Autodesk Fusion 360 part; units mm, degrees
(part 2 of 4)
sketch "TUBE B01 - BACK RING BOTTOM" plane through (0, 0, 0) normal (0, 1, 0) x (1, 0, 0) in component "352307 FRONT - DECOR FRAME DR - BACK RING BOTTOM"
  line L0 (952.9368, -110) -> (1244, -110)
  line L1 (1244, -110) -> (1164, -150)
  line L2 (1164, -150) -> (967.5229, -150)
  line L3 (967.5229, -150) -> (952.9368, -110)
  point P0 (-5000, 5000)
  dimension "d9057" = 5000
  dimension "d9058" = 5000
  dimension "d9060" = 6244
  dimension "d9061" = 6164
  dimension "d9062" = 5967.5229
  dimension "d9064" = 5150
  constraint horizontal L0
  constraint horizontal L2
  measures "d9057" horizontal distance of origin P0
  measures "d9058" vertical distance of origin P0
  measures "d9060" horizontal distance of L0.end P0
  measures "d9061" horizontal distance of L1.end P0
  measures "d9062" horizontal distance of L2.end P0
  measures "d9064" vertical distance of L1.end P0
extrude "EXTRUDE - TUBE B01" add sketch "TUBE B01 - BACK RING BOTTOM" along normal blind 20 from surface at -666.5 separate body makes body 17 in component "352307 FRONT - DECOR FRAME DR - BACK RING BOTTOM"
shell "SHELL - TUBE B01 (ENDS OPEN)" thickness 1.5 removed faces 2 at (962.6609, -659.8333, 136.6667) at (1217.3333, -659.8333, 123.3333) on bodies 17 in component "352307 FRONT - DECOR FRAME DR - BACK RING BOTTOM"
sketch "TUBE B02 - BACK RING BOLT LINE" plane through (0, 0, 0) normal (0, 1, 0) x (1, 0, 0) in component "352308 FRONT - DECOR FRAME DR - BACK RING BOLT LINE"
  line L0 (1244, -110) -> (1244, -2394)
  line L1 (1244, -2394) -> (1164, -2374)
  line L2 (1164, -2374) -> (1164, -150)
  line L3 (1164, -150) -> (1244, -110)
  point P0 (-5000, 5000)
  dimension "d9069" = 5000
  dimension "d9070" = 5000
  dimension "d9071" = 6244
  dimension "d9072" = 6164
  dimension "d9076" = 5150
  constraint vertical L0
  constraint vertical L2
  measures "d9069" horizontal distance of origin P0
  measures "d9070" vertical distance of origin P0
  measures "d9071" horizontal distance of L0.start P0
  measures "d9072" horizontal distance of L1.end P0
  measures "d9076" vertical distance of L2.end P0
extrude "EXTRUDE - TUBE B02" add sketch "TUBE B02 - BACK RING BOLT LINE" along normal blind 20 from surface at -666.5 separate body makes body 18 in component "352308 FRONT - DECOR FRAME DR - BACK RING BOLT LINE"
shell "SHELL - TUBE B02 (ENDS OPEN)" thickness 1.5 removed faces 2 at (1190.6667, -659.8333, 136.6667) at (1217.3333, -659.8333, 2387.3333) on bodies 18 in component "352308 FRONT - DECOR FRAME DR - BACK RING BOLT LINE"
sketch "TUBE B03 - BACK RING TOP" plane through (0, 0, 0) normal (0, 1, 0) x (1, 0, 0) in component "352309 FRONT - DECOR FRAME DR - BACK RING TOP"
  line L0 (1244, -2394) -> (449, -2394)
  line L1 (449, -2394) -> (469, -2374)
  line L2 (469, -2374) -> (1164, -2374)
  line L3 (1164, -2374) -> (1244, -2394)
  point P0 (-5000, 5000)
  dimension "d9081" = 5000
  dimension "d9082" = 5000
  dimension "d9083" = 6244
  dimension "d9084" = 5449
  dimension "d9085" = 5469
  dimension "d9086" = 6164
  constraint horizontal L0
  constraint horizontal L2
  measures "d9081" horizontal distance of origin P0
  measures "d9082" vertical distance of origin P0
  measures "d9083" horizontal distance of L0.start P0
  measures "d9084" horizontal distance of L0.end P0
  measures "d9085" horizontal distance of L1.end P0
  measures "d9086" horizontal distance of L2.end P0
extrude "EXTRUDE - TUBE B03" add sketch "TUBE B03 - BACK RING TOP" along normal blind 20 from surface at -666.5 separate body makes body 19 in component "352309 FRONT - DECOR FRAME DR - BACK RING TOP"
shell "SHELL - TUBE B03 (ENDS OPEN)" thickness 1 removed faces 2 at (1190.6667, -659.8333, 2380.6667) at (455.6667, -659.8333, 2387.3333) on bodies 19 in component "352309 FRONT - DECOR FRAME DR - BACK RING TOP"
sketch "TUBE B04 - BACK RING DT JOINT" plane through (0, 0, 0) normal (0, 1, 0) x (1, 0, 0) in component "352310 FRONT - DECOR FRAME DR - BACK RING DT JOINT"
  line L0 (449, -2394) -> (449, -2120)
  line L1 (449, -2120) -> (469, -2100)
  line L2 (469, -2100) -> (469, -2374)
  line L3 (469, -2374) -> (449, -2394)
  point P0 (-5000, 5000)
  dimension "d9093" = 5000
  dimension "d9094" = 5000
  dimension "d9095" = 5449
  dimension "d9096" = 5469
  dimension "d9099" = 7100
  constraint vertical L0
  constraint vertical L2
  measures "d9093" horizontal distance of origin P0
  measures "d9094" vertical distance of origin P0
  measures "d9095" horizontal distance of L0.start P0
  measures "d9096" horizontal distance of L1.end P0
  measures "d9099" vertical distance of L1.end P0
extrude "EXTRUDE - TUBE B04" add sketch "TUBE B04 - BACK RING DT JOINT" along normal blind 20 from surface at -666.5 separate body makes body 20 in component "352310 FRONT - DECOR FRAME DR - BACK RING DT JOINT"
shell "SHELL - TUBE B04 (ENDS OPEN)" thickness 1 removed faces 2 at (462.3333, -653.1667, 2380.6667) at (455.6667, -653.1667, 2113.3333) on bodies 20 in component "352310 FRONT - DECOR FRAME DR - BACK RING DT JOINT"
sketch "TUBE B05 - BACK RING DT LEDGE" plane through (0, 0, 0) normal (0, 1, 0) x (1, 0, 0) in component "352311 FRONT - DECOR FRAME DR - BACK RING DT LEDGE"
  line L0 (449, -2120) -> (237.9389, -2120)
  line L1 (237.9389, -2120) -> (281.7308, -2100)
  line L2 (281.7308, -2100) -> (469, -2100)
  line L3 (469, -2100) -> (449, -2120)
  point P0 (-5000, 5000)
  dimension "d9105" = 5000
  dimension "d9106" = 5000
  dimension "d9107" = 5449
  dimension "d9108" = 5237.9389
  dimension "d9109" = 5281.7308
  dimension "d9110" = 5469
  dimension "d9112" = 7100
  constraint horizontal L0
  constraint horizontal L2
  measures "d9105" horizontal distance of origin P0
  measures "d9106" vertical distance of origin P0
  measures "d9107" horizontal distance of L0.start P0
  measures "d9108" horizontal distance of L0.end P0
  measures "d9109" horizontal distance of L1.end P0
  measures "d9110" horizontal distance of L2.end P0
  measures "d9112" vertical distance of L1.end P0
extrude "EXTRUDE - TUBE B05" add sketch "TUBE B05 - BACK RING DT LEDGE" along normal blind 20 from surface at -666.5 separate body makes body 21 in component "352311 FRONT - DECOR FRAME DR - BACK RING DT LEDGE"
shell "SHELL - TUBE B05 (ENDS OPEN)" thickness 1.5 removed faces 2 at (462.3333, -659.8333, 2106.6667) at (252.5362, -659.8333, 2113.3333) on bodies 21 in component "352311 FRONT - DECOR FRAME DR - BACK RING DT LEDGE"
sketch "TUBE B06 - BACK RING DIAGONAL" plane through (0, 0, 0) normal (0, 1, 0) x (1, 0, 0) in component "352312 FRONT - DECOR FRAME DR - BACK RING DIAGONAL"
  line L0 (237.9389, -2120) -> (754.6956, -1523.5891)
  line L1 (754.6956, -1523.5891) -> (773.681, -1532.2192)
  line L2 (773.681, -1532.2192) -> (281.7308, -2100)
  line L3 (281.7308, -2100) -> (237.9389, -2120)
  point P0 (-5000, 5000)
  dimension "d9117" = 5000
  dimension "d9118" = 5000
  dimension "d9119" = 5237.9389
  dimension "d9120" = 5754.6956
  dimension "d9121" = 5773.681
  dimension "d9122" = 5281.7308
  dimension "d9124" = 6523.5891
  dimension "d9125" = 6532.2192
  dimension "d9126" = 7100
  measures "d9117" horizontal distance of origin P0
  measures "d9118" vertical distance of origin P0
  measures "d9119" horizontal distance of L0.start P0
  measures "d9120" horizontal distance of L0.end P0
  measures "d9121" horizontal distance of L1.end P0
  measures "d9122" horizontal distance of L2.end P0
  measures "d9124" vertical distance of L0.end P0
  measures "d9125" vertical distance of L1.end P0
  measures "d9126" vertical distance of L2.end P0
extrude "EXTRUDE - TUBE B06" add sketch "TUBE B06 - BACK RING DIAGONAL" along normal blind 20 from surface at -666.5 separate body makes body 22 in component "352312 FRONT - DECOR FRAME DR - BACK RING DIAGONAL"
shell "SHELL - TUBE B06 (ENDS OPEN)" thickness 1.5 removed faces 2 at (267.1335, -659.8333, 2106.6667) at (761.0241, -659.8333, 1526.4658) on bodies 22 in component "352312 FRONT - DECOR FRAME DR - BACK RING DIAGONAL"
sketch "TUBE B07 - BACK RING GLASS EDGE" plane through (0, 0, 0) normal (0, 1, 0) x (1, 0, 0) in component "352313 FRONT - DECOR FRAME DR - BACK RING GLASS EDGE"
  line L0 (754.6956, -1523.5891) -> (952.9368, -110)
  line L1 (952.9368, -110) -> (967.5229, -150)
  line L2 (967.5229, -150) -> (773.681, -1532.2192)
  line L3 (773.681, -1532.2192) -> (754.6956, -1523.5891)
  point P0 (-5000, 5000)
  dimension "d9131" = 5000
  dimension "d9132" = 5000
  dimension "d9133" = 5754.6956
  dimension "d9135" = 5967.5229
  dimension "d9136" = 5773.681
  dimension "d9137" = 6523.5891
  dimension "d9139" = 5150
  dimension "d9140" = 6532.2192
  measures "d9131" horizontal distance of origin P0
  measures "d9132" vertical distance of origin P0
  measures "d9133" horizontal distance of L0.start P0
  measures "d9135" horizontal distance of L1.end P0
  measures "d9136" horizontal distance of L2.end P0
  measures "d9137" vertical distance of L0.start P0
  measures "d9139" vertical distance of L1.end P0
  measures "d9140" vertical distance of L2.end P0
extrude "EXTRUDE - TUBE B07" add sketch "TUBE B07 - BACK RING GLASS EDGE" along normal blind 20 from surface at -666.5 separate body makes body 23 in component "352313 FRONT - DECOR FRAME DR - BACK RING GLASS EDGE"
shell "SHELL - TUBE B07 (ENDS OPEN)" thickness 1.5 removed faces 2 at (767.3526, -659.8333, 1529.3425) at (957.7988, -659.8333, 123.3333) on bodies 23 in component "352313 FRONT - DECOR FRAME DR - BACK RING GLASS EDGE"
sketch "TUBE F07 - FRONT RING CROSS 724" plane through (0, 0, 0) normal (0, 1, 0) x (1, 0, 0) in component "352314 FRONT - DECOR FRAME DR - FRONT RING CROSS 724"
  line L0 (871.599, -834) -> (1029.6995, -834)
  line L1 (1029.6995, -834) -> (1029.6995, -854)
  line L2 (1029.6995, -854) -> (868.7942, -854)
  line L3 (868.7942, -854) -> (871.599, -834)
  point P0 (-5000, 5000)
  dimension "d9145" = 5000
  dimension "d9146" = 5000
  dimension "d9147" = 5871.599
  dimension "d9148" = 6029.6995
  dimension "d9149" = 5868.7942
  dimension "d9150" = 5834
  dimension "d9151" = 5854
  constraint vertical L1
  constraint horizontal L0
  constraint horizontal L2
  measures "d9145" horizontal distance of origin P0
  measures "d9146" vertical distance of origin P0
  measures "d9147" horizontal distance of L0.start P0
  measures "d9148" horizontal distance of L0.end P0
  measures "d9149" horizontal distance of L2.end P0
  measures "d9150" vertical distance of L0.start P0
  measures "d9151" vertical distance of L1.end P0
extrude "EXTRUDE - TUBE F07" add sketch "TUBE F07 - FRONT RING CROSS 724" along normal blind 20 from surface at -844 separate body makes body 24 in component "352314 FRONT - DECOR FRAME DR - FRONT RING CROSS 724"
shell "SHELL - TUBE F07 (ENDS OPEN)" thickness 1 removed faces 2 at (869.7292, -837.3333, 847.3333) at (1029.6995, -837.3333, 840.6667) on bodies 24 in component "352314 FRONT - DECOR FRAME DR - FRONT RING CROSS 724"
sketch "TUBE F08 - FRONT RING FAN BOX SHELF" plane through (0, 0, 0) normal (0, 1, 0) x (1, 0, 0) in component "352315 FRONT - DECOR FRAME DR - FRONT RING FAN BOX SHELF"
  line L0 (688.9595, -1630) -> (1029.6995, -1630)
  line L1 (1029.6995, -1630) -> (1029.6995, -1650)
  line L2 (1029.6995, -1650) -> (671.6306, -1650)
  line L3 (671.6306, -1650) -> (688.9595, -1630)
  point P0 (-5000, 5000)
  dimension "d9156" = 5000
  dimension "d9157" = 5000
  dimension "d9158" = 5688.9595
  dimension "d9159" = 6029.6995
  dimension "d9160" = 5671.6306
  dimension "d9161" = 6630
  dimension "d9162" = 6650
  constraint vertical L1
  constraint horizontal L0
  constraint horizontal L2
  measures "d9156" horizontal distance of origin P0
  measures "d9157" vertical distance of origin P0
  measures "d9158" horizontal distance of L0.start P0
  measures "d9159" horizontal distance of L0.end P0
  measures "d9160" horizontal distance of L2.end P0
  measures "d9161" vertical distance of L0.start P0
  measures "d9162" vertical distance of L1.end P0
extrude "EXTRUDE - TUBE F08" add sketch "TUBE F08 - FRONT RING FAN BOX SHELF" along normal blind 20 from surface at -844 separate body makes body 25 in component "352315 FRONT - DECOR FRAME DR - FRONT RING FAN BOX SHELF"
shell "SHELL - TUBE F08 (ENDS OPEN)" thickness 1.5 removed faces 2 at (677.4069, -837.3333, 1643.3333) at (1029.6995, -837.3333, 1636.6667) on bodies 25 in component "352315 FRONT - DECOR FRAME DR - FRONT RING FAN BOX SHELF"
sketch "TUBE F09 - FRONT RING CROSS OVER THE FAN BOX" plane through (0, 0, 0) normal (0, 1, 0) x (1, 0, 0) in component "352322 FRONT - DECOR FRAME DR - FRONT RING CROSS OVER THE FAN BOX"
  line L0 (451.6766, -1903.8583) -> (1029.6995, -1903.8583)
  line L1 (1029.6995, -1903.8583) -> (1029.6995, -1923.8583)
  line L2 (1029.6995, -1923.8583) -> (434.3477, -1923.8583)
  line L3 (434.3477, -1923.8583) -> (451.6766, -1903.8583)
  point P0 (-5000, 5000)
  dimension "d9167" = 5000
  dimension "d9168" = 5000
  dimension "d9169" = 5451.6766
  dimension "d9170" = 6029.6995
  dimension "d9171" = 5434.3477
  dimension "d9172" = 6903.8583
  dimension "d9173" = 6923.8583
  constraint vertical L1
  constraint horizontal L0
  constraint horizontal L2
  measures "d9167" horizontal distance of origin P0
  measures "d9168" vertical distance of origin P0
  measures "d9169" horizontal distance of L0.start P0
  measures "d9170" horizontal distance of L0.end P0
  measures "d9171" horizontal distance of L2.end P0
  measures "d9172" vertical distance of L0.start P0
  measures "d9173" vertical distance of L1.end P0
extrude "EXTRUDE - TUBE F09" add sketch "TUBE F09 - FRONT RING CROSS OVER THE FAN BOX" along normal blind 20 from surface at -844 separate body makes body 26 in component "352322 FRONT - DECOR FRAME DR - FRONT RING CROSS OVER THE FAN BOX"
shell "SHELL - TUBE F09 (ENDS OPEN)" thickness 1 removed faces 2 at (440.124, -837.3333, 1917.1917) at (1029.6995, -837.3333, 1910.525) on bodies 26 in component "352322 FRONT - DECOR FRAME DR - FRONT RING CROSS OVER THE FAN BOX"
sketch "TUBE B08 - BACK RING BAND" plane through (0, 0, 0) normal (0, 1, 0) x (1, 0, 0) in component "352316 FRONT - DECOR FRAME DR - BACK RING BAND"
  line L0 (469, -2120) -> (1164, -2120)
  line L1 (1164, -2120) -> (1164, -2180)
  line L2 (1164, -2180) -> (469, -2180)
  line L3 (469, -2180) -> (469, -2120)
  point P0 (-5000, 5000)
  dimension "d9178" = 5000
  dimension "d9179" = 5000
  dimension "d9180" = 6164
  dimension "d9181" = 5469
  constraint vertical L1
  constraint vertical L3
  constraint horizontal L0
  constraint horizontal L2
  measures "d9178" horizontal distance of origin P0
  measures "d9179" vertical distance of origin P0
  measures "d9180" horizontal distance of L0.end P0
  measures "d9181" horizontal distance of L2.end P0
extrude "EXTRUDE - TUBE B08" add sketch "TUBE B08 - BACK RING BAND" along normal blind 20 from surface at -666.5 separate body makes body 27 in component "352316 FRONT - DECOR FRAME DR - BACK RING BAND"
shell "SHELL - TUBE B08 (ENDS OPEN)" thickness 1.5 removed faces 2 at (469, -659.8333, 2160) at (1164, -659.8333, 2140) on bodies 27 in component "352316 FRONT - DECOR FRAME DR - BACK RING BAND"
sketch "TUBE C01 - FACET TUBE BOTTOM" plane through (0, 0, 0) normal (0, 0, 1) x (1, 0, 0) in component "352317 FRONT - DECOR FRAME DR - FACET TUBE - 3 OFF"
  line L0 (1049.6995, -844) -> (1244, -669.3258)
  line L1 (1244, -669.3258) -> (1244, -666.5)
  line L2 (1244, -666.5) -> (1217.2278, -666.5)
  line L3 (1217.2278, -666.5) -> (1049.6995, -817.1063)
  line L4 (1049.6995, -817.1063) -> (1049.6995, -844)
  point P0 (-5000, -5000)
  dimension "d9188" = 5000
  dimension "d9189" = 5000
  dimension "d9190" = 6244
  dimension "d9191" = 6217.2278
  dimension "d9192" = 6049.6995
  dimension "d9193" = 4156
  dimension "d9194" = 4330.6742
  dimension "d9195" = 4333.5
  dimension "d9196" = 4182.8937
  constraint vertical L1
  constraint vertical L4
  constraint horizontal L2
  measures "d9188" horizontal distance of origin P0
  measures "d9189" vertical distance of origin P0
  measures "d9190" horizontal distance of L0.end P0
  measures "d9191" horizontal distance of L2.end P0
  measures "d9192" horizontal distance of L3.end P0
  measures "d9193" vertical distance of L0.start P0
  measures "d9194" vertical distance of L0.end P0
  measures "d9195" vertical distance of L1.end P0
  measures "d9196" vertical distance of L3.end P0
extrude "EXTRUDE - TUBE C01" add sketch "TUBE C01 - FACET TUBE BOTTOM" along normal blind 20 from surface at 110 separate body makes body 28 in component "352317 FRONT - DECOR FRAME DR - FACET TUBE - 3 OFF"
shell "SHELL - TUBE C01 (ENDS OPEN)" thickness 1 removed faces 3 at (1235.0759, -666.5, 123.3333) at (1244, -668.3839, 116.6667) at (1049.6995, -826.0708, 116.6667) on bodies 28 in component "352317 FRONT - DECOR FRAME DR - FACET TUBE - 3 OFF"
sketch "TUBE C03 - FACET TUBE FAN BOX SHELF" plane through (0, 0, 0) normal (0, 0, 1) x (1, 0, 0) in component "352318 FRONT - DECOR FRAME DR - FACET TUBE FAN BOX SHELF"
  line L0 (1049.6995, -844) -> (1244, -669.3258)
  line L1 (1244, -669.3258) -> (1244, -666.5)
  line L2 (1244, -666.5) -> (1217.2278, -666.5)
  line L3 (1217.2278, -666.5) -> (1049.6995, -817.1063)
  line L4 (1049.6995, -817.1063) -> (1049.6995, -844)
  point P0 (-5000, -5000)
  dimension "d9201" = 5000
  dimension "d9202" = 5000
  dimension "d9203" = 6244
  dimension "d9204" = 6217.2278
  dimension "d9205" = 6049.6995
  dimension "d9206" = 4156
  dimension "d9207" = 4330.6742
  dimension "d9208" = 4333.5
  dimension "d9209" = 4182.8937
  constraint vertical L1
  constraint vertical L4
  constraint horizontal L2
  measures "d9201" horizontal distance of origin P0
  measures "d9202" vertical distance of origin P0
  measures "d9203" horizontal distance of L0.end P0
  measures "d9204" horizontal distance of L2.end P0
  measures "d9205" horizontal distance of L3.end P0
  measures "d9206" vertical distance of L0.start P0
  measures "d9207" vertical distance of L0.end P0
  measures "d9208" vertical distance of L1.end P0
  measures "d9209" vertical distance of L3.end P0
extrude "EXTRUDE - TUBE C03" add sketch "TUBE C03 - FACET TUBE FAN BOX SHELF" along normal blind 20 from surface at 1630 separate body makes body 29 in component "352318 FRONT - DECOR FRAME DR - FACET TUBE FAN BOX SHELF"
shell "SHELL - TUBE C03 (ENDS OPEN)" thickness 1.5 removed faces 3 at (1235.0759, -666.5, 1643.3333) at (1244, -668.3839, 1636.6667) at (1049.6995, -826.0708, 1636.6667) on bodies 29 in component "352318 FRONT - DECOR FRAME DR - FACET TUBE FAN BOX SHELF"
ref_plane "WorkPlane1" through (0, 0, 1820) normal (0, 0, 1) x (1, 0, 0) in component "351306 FRONT - DECOR FRAME - DR"
ref_plane "WorkPlane2" through (0, 0, 2067.7167) normal (0, 0, 1) x (1, 0, 0) in component "351306 FRONT - DECOR FRAME - DR"
sketch "TUBE C06 - CHAMFER TUBE LEFT" plane through (0, 0, 0) normal (1, 0, 0) x (0, 0, -1) in component "352319 FRONT - DECOR FRAME DR - CHAMFER TUBE - 2 OFF"
  line L0 (-2197.7167, -844) -> (-2394, -669.3078)
  line L1 (-2394, -669.3078) -> (-2394, -666.5)
  line L2 (-2394, -666.5) -> (-2367.0719, -666.5)
  line L3 (-2367.0719, -666.5) -> (-2197.7167, -817.2261)
  line L4 (-2197.7167, -817.2261) -> (-2197.7167, -844)
  point P0 (5000, -5000)
  dimension "d9226" = 5000
  dimension "d9227" = 5000
  dimension "d9229" = 7367.0719
  dimension "d9230" = 7197.7167
  dimension "d9231" = 4156
  dimension "d9232" = 4330.6922
  dimension "d9233" = 4333.5
  dimension "d9234" = 4182.7739
  constraint vertical L1
  constraint vertical L4
  constraint horizontal L2
  measures "d9226" horizontal distance of origin P0
  measures "d9227" vertical distance of origin P0
  measures "d9229" horizontal distance of L2.end P0
  measures "d9230" horizontal distance of L3.end P0
  measures "d9231" vertical distance of L0.start P0
  measures "d9232" vertical distance of L0.end P0
  measures "d9233" vertical distance of L1.end P0
  measures "d9234" vertical distance of L3.end P0
extrude "EXTRUDE - TUBE C06" add sketch "TUBE C06 - CHAMFER TUBE LEFT" along normal blind 20 from surface at 469 separate body makes body 30 in component "352319 FRONT - DECOR FRAME DR - CHAMFER TUBE - 2 OFF"
shell "SHELL - TUBE C06 (ENDS OPEN)" thickness 1 removed faces 3 at (475.6667, -826.1508, 2197.7167) at (482.3333, -668.3719, 2394) at (482.3333, -666.5, 2385.024) on bodies 30 in component "352319 FRONT - DECOR FRAME DR - CHAMFER TUBE - 2 OFF"
ref_plane "WorkPlane3" through (540.6995, 0, 0) normal (1, 0, 0) x (0, 1, 0) in component "351306 FRONT - DECOR FRAME - DR"
sketch "TUBE C09 - DT JOINT TUBE SLANTED" plane through (0, 0, 0) normal (0, 0, 1) x (1, 0, 0) in component "352320 FRONT - DECOR FRAME DR - DT JOINT TUBE SLANTED"
  line L0 (261.9888, -824) -> (455.7669, -666.5)
  line L1 (455.7669, -666.5) -> (487.4763, -666.5)
  line L2 (487.4763, -666.5) -> (293.6983, -824)
  line L3 (293.6983, -824) -> (261.9888, -824)
  point P0 (-5000, -5000)
  dimension "d9245" = 5000
  dimension "d9246" = 5000
  dimension "d9247" = 5261.9888
  dimension "d9248" = 5455.7669
  dimension "d9249" = 5487.4763
  dimension "d9250" = 5293.6983
  dimension "d9251" = 4333.5
  dimension "d9252" = 4176
  constraint horizontal L1
  constraint horizontal L3
  measures "d9245" horizontal distance of origin P0
  measures "d9246" vertical distance of origin P0
  measures "d9247" horizontal distance of L0.start P0
  measures "d9248" horizontal distance of L0.end P0
  measures "d9249" horizontal distance of L1.end P0
  measures "d9250" horizontal distance of L2.end P0
  measures "d9251" vertical distance of L0.end P0
  measures "d9252" vertical distance of L2.end P0
extrude "EXTRUDE - TUBE C09" add sketch "TUBE C09 - DT JOINT TUBE SLANTED" along normal blind 20 from surface at 2120 separate body makes body 31 in component "352320 FRONT - DECOR FRAME DR - DT JOINT TUBE SLANTED"
shell "SHELL - TUBE C09 (ENDS OPEN)" thickness 1 removed faces 2 at (283.1284, -824, 2126.6667) at (466.3367, -666.5, 2133.3333) on bodies 31 in component "352320 FRONT - DECOR FRAME DR - DT JOINT TUBE SLANTED"
sketch "HOLES - J-FRONT-01 RIVNUT TAILS AND BOLT TIPS (6)" plane through (0, 0, 0) normal (0, 1, 0) x (1, 0, 0) in component "352308 FRONT - DECOR FRAME DR - BACK RING BOLT LINE"
  circle A0 centre (1224, -332.26) radius 7
  circle A1 centre (1224, -683.63) radius 7
  circle A2 centre (1224, -1035) radius 7
  circle A3 centre (1224, -1477.26) radius 7
  circle A4 centre (1224, -1828.63) radius 7
  circle A5 centre (1224, -2180) radius 7
  point P0 (-5000, 5000)
  dimension "d9257" = 5000
  dimension "d9258" = 5000
  dimension "d9260" = 5332.26
  dimension "d9261" = 14
  dimension "d9263" = 5683.63
  dimension "d9264" = 14
  dimension "d9266" = 6035
  dimension "d9267" = 14
  dimension "d9269" = 6477.26
  dimension "d9270" = 14
  dimension "d9272" = 6828.63
  dimension "d9273" = 14
  dimension "d9275" = 7180
  dimension "d9276" = 14
  measures "d9257" horizontal distance of origin P0
  measures "d9258" vertical distance of origin P0
  measures "d9260" vertical distance of P0 A0.centre
  measures "d9261" diameter of A0
  measures "d9263" vertical distance of P0 A1.centre
  measures "d9264" diameter of A1
  measures "d9266" vertical distance of P0 A2.centre
  measures "d9267" diameter of A2
  measures "d9269" vertical distance of P0 A3.centre
  measures "d9270" diameter of A3
  measures "d9272" vertical distance of P0 A4.centre
  measures "d9273" diameter of A4
  measures "d9275" vertical distance of P0 A5.centre
  measures "d9276" diameter of A5
extrude "CUT - J-FRONT-01 RIVNUT TAILS AND BOLT TIPS (6)" cut sketch "HOLES - J-FRONT-01 RIVNUT TAILS AND BOLT TIPS (6)" along normal blind 3 from surface at -649 bodies 18 in component "352308 FRONT - DECOR FRAME DR - BACK RING BOLT LINE"
sketch "HOLES - THE INNER FACE PANEL'S RIVNUTS ON B01 (2)" plane through (0, 0, 0) normal (0, 1, 0) x (1, 0, 0) in component "352307 FRONT - DECOR FRAME DR - BACK RING BOTTOM"
  circle A0 centre (1000.2299, -130) radius 5
  circle A1 centre (1146, -130) radius 5
  point P0 (-5000, 5000)
  dimension "d9280" = 5000
  dimension "d9281" = 5000
  dimension "d9282" = 6000.2299
  dimension "d9283" = 5130
  dimension "d9284" = 10
  dimension "d9285" = 6146
  dimension "d9286" = 5130
  dimension "d9287" = 10
  measures "d9280" horizontal distance of origin P0
  measures "d9281" vertical distance of origin P0
  measures "d9282" horizontal distance of P0 A0.centre
  measures "d9283" vertical distance of P0 A0.centre
  measures "d9284" diameter of A0
  measures "d9285" horizontal distance of P0 A1.centre
  measures "d9286" vertical distance of P0 A1.centre
  measures "d9287" diameter of A1
extrude "CUT - THE INNER FACE PANEL'S RIVNUTS ON B01 (2)" cut sketch "HOLES - THE INNER FACE PANEL'S RIVNUTS ON B01 (2)" along normal blind 3 from surface at -649 bodies 17 in component "352307 FRONT - DECOR FRAME DR - BACK RING BOTTOM"
sketch "HOLES - THE INNER FACE PANEL'S RIVNUTS ON B02 (6)" plane through (0, 0, 0) normal (0, 1, 0) x (1, 0, 0) in component "352308 FRONT - DECOR FRAME DR - BACK RING BOLT LINE"
  circle A0 centre (1186, -170) radius 5
  circle A1 centre (1186, -556.2) radius 5
  circle A2 centre (1186, -942.4) radius 5
  circle A3 centre (1186, -1328.6) radius 5
  circle A4 centre (1186, -1714.8) radius 5
  circle A5 centre (1186, -2101) radius 5
  point P0 (-5000, 5000)
  dimension "d9291" = 5000
  dimension "d9292" = 5000
  dimension "d9293" = 6186
  dimension "d9294" = 5170
  dimension "d9295" = 10
  dimension "d9296" = 6186
  dimension "d9297" = 5556.2
  dimension "d9298" = 10
  dimension "d9299" = 6186
  dimension "d9300" = 5942.4
  dimension "d9301" = 10
  dimension "d9302" = 6186
  dimension "d9303" = 6328.6
  dimension "d9304" = 10
  dimension "d9305" = 6186
  dimension "d9306" = 6714.8
  dimension "d9307" = 10
  dimension "d9308" = 6186
  dimension "d9309" = 7101
  dimension "d9310" = 10
  measures "d9291" horizontal distance of origin P0
  measures "d9292" vertical distance of origin P0
  measures "d9293" horizontal distance of P0 A0.centre
  measures "d9294" vertical distance of P0 A0.centre
  measures "d9295" diameter of A0
  measures "d9296" horizontal distance of P0 A1.centre
  measures "d9297" vertical distance of P0 A1.centre
  measures "d9298" diameter of A1
  measures "d9299" horizontal distance of P0 A2.centre
  measures "d9300" vertical distance of P0 A2.centre
  measures "d9301" diameter of A2
  measures "d9302" horizontal distance of P0 A3.centre
  measures "d9303" vertical distance of P0 A3.centre
  measures "d9304" diameter of A3
  measures "d9305" horizontal distance of P0 A4.centre
  measures "d9306" vertical distance of P0 A4.centre
  measures "d9307" diameter of A4
  measures "d9308" horizontal distance of P0 A5.centre
  measures "d9309" vertical distance of P0 A5.centre
  measures "d9310" diameter of A5
extrude "CUT - THE INNER FACE PANEL'S RIVNUTS ON B02 (6)" cut sketch "HOLES - THE INNER FACE PANEL'S RIVNUTS ON B02 (6)" along normal blind 3 from surface at -649 bodies 18 in component "352308 FRONT - DECOR FRAME DR - BACK RING BOLT LINE"
sketch "HOLES - THE INNER FACE PANEL'S RIVNUTS ON B08 (3)" plane through (0, 0, 0) normal (0, 1, 0) x (1, 0, 0) in component "352316 FRONT - DECOR FRAME DR - BACK RING BAND"
  circle A0 centre (1143.5, -2141) radius 5
  circle A1 centre (821.25, -2141) radius 5
  circle A2 centre (499, -2141) radius 5
  point P0 (-5000, 5000)
  dimension "d9314" = 5000
  dimension "d9315" = 5000
  dimension "d9316" = 6143.5
  dimension "d9317" = 7141
  dimension "d9318" = 10
  dimension "d9319" = 5821.25
  dimension "d9320" = 7141
  dimension "d9321" = 10
  dimension "d9322" = 5499
  dimension "d9323" = 7141
  dimension "d9324" = 10
  measures "d9314" horizontal distance of origin P0
  measures "d9315" vertical distance of origin P0
  measures "d9316" horizontal distance of P0 A0.centre
  measures "d9317" vertical distance of P0 A0.centre
  measures "d9318" diameter of A0
  measures "d9319" horizontal distance of P0 A1.centre
  measures "d9320" vertical distance of P0 A1.centre
  measures "d9321" diameter of A1
  measures "d9322" horizontal distance of P0 A2.centre
  measures "d9323" vertical distance of P0 A2.centre
  measures "d9324" diameter of A2
extrude "CUT - THE INNER FACE PANEL'S RIVNUTS ON B08 (3)" cut sketch "HOLES - THE INNER FACE PANEL'S RIVNUTS ON B08 (3)" along normal blind 3 from surface at -649 bodies 27 in component "352316 FRONT - DECOR FRAME DR - BACK RING BAND"
sketch "HOLES - THE INNER FACE PANEL'S RIVNUTS ON B05 (2)" plane through (0, 0, 0) normal (0, 1, 0) x (1, 0, 0) in component "352311 FRONT - DECOR FRAME DR - BACK RING DT LEDGE"
  circle A0 centre (419, -2110) radius 5
  circle A1 centre (299.8348, -2110) radius 5
  point P0 (-5000, 5000)
  dimension "d9328" = 5000
  dimension "d9329" = 5000
  dimension "d9330" = 5419
  dimension "d9331" = 7110
  dimension "d9332" = 10
  dimension "d9333" = 5299.8348
  dimension "d9334" = 7110
  dimension "d9335" = 10
  measures "d9328" horizontal distance of origin P0
  measures "d9329" vertical distance of origin P0
  measures "d9330" horizontal distance of P0 A0.centre
  measures "d9331" vertical distance of P0 A0.centre
  measures "d9332" diameter of A0
  measures "d9333" horizontal distance of P0 A1.centre
  measures "d9334" vertical distance of P0 A1.centre
  measures "d9335" diameter of A1
extrude "CUT - THE INNER FACE PANEL'S RIVNUTS ON B05 (2)" cut sketch "HOLES - THE INNER FACE PANEL'S RIVNUTS ON B05 (2)" along normal blind 3 from surface at -649 bodies 21 in component "352311 FRONT - DECOR FRAME DR - BACK RING DT LEDGE"
sketch "HOLES - THE INNER FACE PANEL'S RIVNUTS ON B06 (3)" plane through (0, 0, 0) normal (0, 1, 0) x (1, 0, 0) in component "352312 FRONT - DECOR FRAME DR - BACK RING DIAGONAL"
  circle A0 centre (286.0282, -2079.7691) radius 5
  circle A1 centre (512.0116, -1818.9521) radius 5
  circle A2 centre (737.995, -1558.135) radius 5
  point P0 (-5000, 5000)
  dimension "d9339" = 5000
  dimension "d9340" = 5000
  dimension "d9341" = 5286.0282
  dimension "d9342" = 7079.7691
  dimension "d9343" = 10
  dimension "d9344" = 5512.0116
  dimension "d9345" = 6818.9521
  dimension "d9346" = 10
  dimension "d9347" = 5737.995
  dimension "d9348" = 6558.135
  dimension "d9349" = 10
  measures "d9339" horizontal distance of origin P0
  measures "d9340" vertical distance of origin P0
  measures "d9341" horizontal distance of P0 A0.centre
  measures "d9342" vertical distance of P0 A0.centre
  measures "d9343" diameter of A0
  measures "d9344" horizontal distance of P0 A1.centre
  measures "d9345" vertical distance of P0 A1.centre
  measures "d9346" diameter of A1
  measures "d9347" horizontal distance of P0 A2.centre
  measures "d9348" vertical distance of P0 A2.centre
  measures "d9349" diameter of A2
extrude "CUT - THE INNER FACE PANEL'S RIVNUTS ON B06 (3)" cut sketch "HOLES - THE INNER FACE PANEL'S RIVNUTS ON B06 (3)" along normal blind 3 from surface at -649 bodies 22 in component "352312 FRONT - DECOR FRAME DR - BACK RING DIAGONAL"
sketch "HOLES - THE INNER FACE PANEL'S RIVNUTS ON B07 (5)" plane through (0, 0, 0) normal (0, 1, 0) x (1, 0, 0) in component "352313 FRONT - DECOR FRAME DR - BACK RING GLASS EDGE"
  circle A0 centre (769.7436, -1488.2918) radius 5
  circle A1 centre (812.0577, -1186.5645) radius 5
  circle A2 centre (854.3718, -884.8373) radius 5
  circle A3 centre (896.6859, -583.11) radius 5
  circle A4 centre (939, -281.3828) radius 5
  point P0 (-5000, 5000)
  dimension "d9353" = 5000
  dimension "d9354" = 5000
  dimension "d9355" = 5769.7436
  dimension "d9356" = 6488.2918
  dimension "d9357" = 10
  dimension "d9358" = 5812.0577
  dimension "d9359" = 6186.5645
  dimension "d9360" = 10
  dimension "d9361" = 5854.3718
  dimension "d9362" = 5884.8373
  dimension "d9363" = 10
  dimension "d9364" = 5896.6859
  dimension "d9365" = 5583.11
  dimension "d9366" = 10
  dimension "d9367" = 5939
  dimension "d9368" = 5281.3828
  dimension "d9369" = 10
  measures "d9353" horizontal distance of origin P0
  measures "d9354" vertical distance of origin P0
  measures "d9355" horizontal distance of P0 A0.centre
  measures "d9356" vertical distance of P0 A0.centre
  measures "d9357" diameter of A0
  measures "d9358" horizontal distance of P0 A1.centre
  measures "d9359" vertical distance of P0 A1.centre
  measures "d9360" diameter of A1
  measures "d9361" horizontal distance of P0 A2.centre
  measures "d9362" vertical distance of P0 A2.centre
  measures "d9363" diameter of A2
  measures "d9364" horizontal distance of P0 A3.centre
  measures "d9365" vertical distance of P0 A3.centre
  measures "d9366" diameter of A3
  measures "d9367" horizontal distance of P0 A4.centre
  measures "d9368" vertical distance of P0 A4.centre
  measures "d9369" diameter of A4
extrude "CUT - THE INNER FACE PANEL'S RIVNUTS ON B07 (5)" cut sketch "HOLES - THE INNER FACE PANEL'S RIVNUTS ON B07 (5)" along normal blind 3 from surface at -649 bodies 23 in component "352313 FRONT - DECOR FRAME DR - BACK RING GLASS EDGE"
sketch "HOLES - J-FRONT-02 SPIGOT ROUND AND SLOT ENDS" plane through (0, 0, 0) normal (0, 0, 1) x (1, 0, 0) in component "352307 FRONT - DECOR FRAME DR - BACK RING BOTTOM"
  circle A0 centre (1050, -656.5) radius 4.25
  circle A1 centre (1144.25, -656.5) radius 4.25
  circle A2 centre (1149.75, -656.5) radius 4.25
  point P0 (-5000, -5000)
  dimension "d9373" = 5000
  dimension "d9374" = 5000
  dimension "d9375" = 6050
  dimension "d9376" = 4343.5
  dimension "d9377" = 8.5
  dimension "d9378" = 6144.25
  dimension "d9379" = 4343.5
  dimension "d9380" = 8.5
  dimension "d9381" = 6149.75
  dimension "d9382" = 4343.5
  dimension "d9383" = 8.5
  measures "d9373" horizontal distance of origin P0
  measures "d9374" vertical distance of origin P0
  measures "d9375" horizontal distance of P0 A0.centre
  measures "d9376" vertical distance of P0 A0.centre
  measures "d9377" diameter of A0
  measures "d9378" horizontal distance of P0 A1.centre
  measures "d9379" vertical distance of P0 A1.centre
  measures "d9380" diameter of A1
  measures "d9381" horizontal distance of P0 A2.centre
  measures "d9382" vertical distance of P0 A2.centre
  measures "d9383" diameter of A2
extrude "CUT - J-FRONT-02 SPIGOT HOLE AND SLOT ENDS" cut sketch "HOLES - J-FRONT-02 SPIGOT ROUND AND SLOT ENDS" along normal blind 3 from surface at 109 bodies 17 in component "352307 FRONT - DECOR FRAME DR - BACK RING BOTTOM"
sketch "SLOT - J-FRONT-02 SPIGOT (MIDDLE)" plane through (0, 0, 0) normal (0, 0, 1) x (1, 0, 0) in component "352307 FRONT - DECOR FRAME DR - BACK RING BOTTOM"
  line L0 (1144.25, -660.75) -> (1149.75, -660.75)
  line L1 (1149.75, -660.75) -> (1149.75, -652.25)
  line L2 (1149.75, -652.25) -> (1144.25, -652.25)
  line L3 (1144.25, -652.25) -> (1144.25, -660.75)
  point P0 (-5000, -5000)
  dimension "d9387" = 5000
  dimension "d9388" = 5000
  dimension "d9389" = 6149.75
  dimension "d9390" = 6144.25
  dimension "d9391" = 4339.25
  dimension "d9392" = 4347.75
  constraint vertical L1
  constraint vertical L3
  constraint horizontal L0
  constraint horizontal L2
  measures "d9387" horizontal distance of origin P0
  measures "d9388" vertical distance of origin P0
  measures "d9389" horizontal distance of L0.end P0
  measures "d9390" horizontal distance of L2.end P0
  measures "d9391" vertical distance of L0.start P0
  measures "d9392" vertical distance of L1.end P0
extrude "CUT - J-FRONT-02 SPIGOT SLOT MIDDLE" cut sketch "SLOT - J-FRONT-02 SPIGOT (MIDDLE)" along normal blind 3 from surface at 109 bodies 17 in component "352307 FRONT - DECOR FRAME DR - BACK RING BOTTOM"
sketch "HOLES - J-FRONT-03 SPIGOT RIVNUTS (2)" plane through (0, 0, 0) normal (0, 0, 1) x (1, 0, 0) in component "352311 FRONT - DECOR FRAME DR - BACK RING DT LEDGE"
  circle A0 centre (270, -657.88) radius 5
  circle A1 centre (410, -657.88) radius 5
  point P0 (-5000, -5000)
  dimension "d9396" = 5000
  dimension "d9397" = 5000
  dimension "d9398" = 5270
  dimension "d9400" = 10
  dimension "d9401" = 5410
  dimension "d9403" = 10
  measures "d9396" horizontal distance of origin P0
  measures "d9397" vertical distance of origin P0
  measures "d9398" horizontal distance of P0 A0.centre
  measures "d9400" diameter of A0
  measures "d9401" horizontal distance of P0 A1.centre
  measures "d9403" diameter of A1
extrude "CUT - J-FRONT-03 SPIGOT RIVNUTS" cut sketch "HOLES - J-FRONT-03 SPIGOT RIVNUTS (2)" along normal blind 2.7 from surface at 2118.3 bodies 21 in component "352311 FRONT - DECOR FRAME DR - BACK RING DT LEDGE"
component "350004 FRONT - AIR SUPPLY ASSY - DR - RESERVED AIR SPACE" placed x (1, 0, 0) y (0, 1, 0) z (0, 0, 1) at (0, 0, 0)
component "351301 FRONT - DECOR SKIN - DR" placed x (1, 0, 0) y (0, 1, 0) z (0, 0, 1) at (0, 0, 0)
component "351302 FRONT - DECOR BACK PLATE - DR" placed x (1, 0, 0) y (0, 1, 0) z (0, 0, 1) at (0, 0, 0)
component "351305 FRONT - DECOR INNER FACE PANEL - DR - REMOVABLE" placed x (1, 0, 0) y (0, 1, 0) z (0, 0, 1) at (0, 0, 0)
component "351304 FRONT - DECOR INNER PANEL FELT - DR" placed x (1, 0, 0) y (0, 1, 0) z (0, 0, 1) at (0, 0, 0)
component "848013 SEALS - ACCESS PANEL SEAL - 4.0 THICK - VERY SOFT FOAM PSA" placed x (1, 0, 0) y (0, 1, 0) z (0, 0, 1) at (0, 0, 0)
component "351306 FRONT - DECOR FRAME - DR" placed x (1, 0, 0) y (0, 1, 0) z (0, 0, 1) at (0, 0, 0)
component "351402 FRONT - AIR INTAKE RISER - DR - RESERVED AIR SPACE" placed x (1, 0, 0) y (0, 1, 0) z (0, 0, 1) at (0, 0, 0) in component "350004 FRONT - AIR SUPPLY ASSY - DR - RESERVED AIR SPACE"
component "351403 FRONT - AIR TRANSITION - LOWER - DR - RESERVED AIR SPACE" placed x (1, 0, 0) y (0, 1, 0) z (0, 0, 1) at (0, 0, 0) in component "350004 FRONT - AIR SUPPLY ASSY - DR - RESERVED AIR SPACE"
component "351404 FRONT - SUPPLY FAN BOX - DR - RESERVED AIR SPACE" placed x (1, 0, 0) y (0, 1, 0) z (0, 0, 1) at (0, 0, 0) in component "350004 FRONT - AIR SUPPLY ASSY - DR - RESERVED AIR SPACE"
component "351405 FRONT - AIR TRANSITION - UPPER - DR - RESERVED AIR SPACE" placed x (1, 0, 0) y (0, 1, 0) z (0, 0, 1) at (0, 0, 0) in component "350004 FRONT - AIR SUPPLY ASSY - DR - RESERVED AIR SPACE"
component "352301 FRONT - DECOR FRAME DR - FRONT RING BOTTOM" placed x (1, 0, 0) y (0, 1, 0) z (0, 0, 1) at (0, 0, 0) in component "351306 FRONT - DECOR FRAME - DR"
component "352302 FRONT - DECOR FRAME DR - FRONT RING FACET SIDE" placed x (1, 0, 0) y (0, 1, 0) z (0, 0, 1) at (0, 0, 0) in component "351306 FRONT - DECOR FRAME - DR"
component "352303 FRONT - DECOR FRAME DR - FRONT RING TOP" placed x (1, 0, 0) y (0, 1, 0) z (0, 0, 1) at (0, 0, 0) in component "351306 FRONT - DECOR FRAME - DR"
component "352304 FRONT - DECOR FRAME DR - FRONT RING DT JOINT" placed x (1, 0, 0) y (0, 1, 0) z (0, 0, 1) at (0, 0, 0) in component "351306 FRONT - DECOR FRAME - DR"
component "352305 FRONT - DECOR FRAME DR - FRONT RING DIAGONAL" placed x (1, 0, 0) y (0, 1, 0) z (0, 0, 1) at (0, 0, 0) in component "351306 FRONT - DECOR FRAME - DR"
component "352306 FRONT - DECOR FRAME DR - FRONT RING GLASS EDGE" placed x (1, 0, 0) y (0, 1, 0) z (0, 0, 1) at (0, 0, 0) in component "351306 FRONT - DECOR FRAME - DR"
component "352307 FRONT - DECOR FRAME DR - BACK RING BOTTOM" placed x (1, 0, 0) y (0, 1, 0) z (0, 0, 1) at (0, 0, 0) in component "351306 FRONT - DECOR FRAME - DR"
component "352308 FRONT - DECOR FRAME DR - BACK RING BOLT LINE" placed x (1, 0, 0) y (0, 1, 0) z (0, 0, 1) at (0, 0, 0) in component "351306 FRONT - DECOR FRAME - DR"
component "352309 FRONT - DECOR FRAME DR - BACK RING TOP" placed x (1, 0, 0) y (0, 1, 0) z (0, 0, 1) at (0, 0, 0) in component "351306 FRONT - DECOR FRAME - DR"
component "352310 FRONT - DECOR FRAME DR - BACK RING DT JOINT" placed x (1, 0, 0) y (0, 1, 0) z (0, 0, 1) at (0, 0, 0) in component "351306 FRONT - DECOR FRAME - DR"
component "352311 FRONT - DECOR FRAME DR - BACK RING DT LEDGE" placed x (1, 0, 0) y (0, 1, 0) z (0, 0, 1) at (0, 0, 0) in component "351306 FRONT - DECOR FRAME - DR"
component "352312 FRONT - DECOR FRAME DR - BACK RING DIAGONAL" placed x (1, 0, 0) y (0, 1, 0) z (0, 0, 1) at (0, 0, 0) in component "351306 FRONT - DECOR FRAME - DR"
component "352313 FRONT - DECOR FRAME DR - BACK RING GLASS EDGE" placed x (1, 0, 0) y (0, 1, 0) z (0, 0, 1) at (0, 0, 0) in component "351306 FRONT - DECOR FRAME - DR"
component "352314 FRONT - DECOR FRAME DR - FRONT RING CROSS 724" placed x (1, 0, 0) y (0, 1, 0) z (0, 0, 1) at (0, 0, 0) in component "351306 FRONT - DECOR FRAME - DR"
component "352315 FRONT - DECOR FRAME DR - FRONT RING FAN BOX SHELF" placed x (1, 0, 0) y (0, 1, 0) z (0, 0, 1) at (0, 0, 0) in component "351306 FRONT - DECOR FRAME - DR"
component "352322 FRONT - DECOR FRAME DR - FRONT RING CROSS OVER THE FAN BOX" placed x (1, 0, 0) y (0, 1, 0) z (0, 0, 1) at (0, 0, 0) in component "351306 FRONT - DECOR FRAME - DR"
component "352316 FRONT - DECOR FRAME DR - BACK RING BAND" placed x (1, 0, 0) y (0, 1, 0) z (0, 0, 1) at (0, 0, 0) in component "351306 FRONT - DECOR FRAME - DR"
component "352317 FRONT - DECOR FRAME DR - FACET TUBE - 3 OFF" placed x (1, 0, 0) y (0, 1, 0) z (0, 0, 1) at (0, 0, 0) in component "351306 FRONT - DECOR FRAME - DR"
component "352318 FRONT - DECOR FRAME DR - FACET TUBE FAN BOX SHELF" placed x (1, 0, 0) y (0, 1, 0) z (0, 0, 1) at (0, 0, 0) in component "351306 FRONT - DECOR FRAME - DR"
component "352317 FRONT - DECOR FRAME DR - FACET TUBE - 3 OFF" placed x (1, 0, 0) y (0, 1, 0) z (0, 0, 1) at (0, 0, 1820) in component "351306 FRONT - DECOR FRAME - DR"
component "352317 FRONT - DECOR FRAME DR - FACET TUBE - 3 OFF" placed x (1, 0, 0) y (0, 1, 0) z (0, 0, 1) at (0, 0, 2067.7167) in component "351306 FRONT - DECOR FRAME - DR"
component "352319 FRONT - DECOR FRAME DR - CHAMFER TUBE - 2 OFF" placed x (1, 0, 0) y (0, 1, 0) z (0, 0, 1) at (0, 0, 0) in component "351306 FRONT - DECOR FRAME - DR"
component "352319 FRONT - DECOR FRAME DR - CHAMFER TUBE - 2 OFF" placed x (1, 0, 0) y (0, 1, 0) z (0, 0, 1) at (540.6995, 0, 0) in component "351306 FRONT - DECOR FRAME - DR"
component "352320 FRONT - DECOR FRAME DR - DT JOINT TUBE SLANTED" placed x (1, 0, 0) y (0, 1, 0) z (0, 0, 1) at (0, 0, 0) in component "351306 FRONT - DECOR FRAME - DR"
equation "pod_w = 2500 mm" comment "SKELETON P04 DECIDED: D-01; conventions s4 (X = +-1250)"
equation "pod_d = 1700 mm" comment "SKELETON P04 DECIDED: D-01; conventions s4 (Y = +-850)"
equation "pod_h = 2400 mm" comment "SKELETON P04 DECIDED: D-21 (room floor to roof skin top)"
equation "glide_h = 10 mm" comment "SKELETON P04 ASSUMPTION: layout study inputs.py glide_h"
equation "band_h = 100 mm" comment "SKELETON P04 SOURCE: layout study B1 list B-BAND 100x40; inputs.py base_h"
equation "band_t = 40 mm" comment "SKELETON P04 SOURCE: layout study B1 list B-BAND 100x40"
equation "skin_t = 3 mm" comment "SKELETON P04 DECIDED: ACP skin, walls and ceiling (D-16; PM ruling 2026-10-31 on outer_t)"
equation "bond_t = 3 mm" comment "SKELETON P04 DECIDED: bond line between the ACP and the frame (PM ruling 2026-10-31 on outer_t)"
equation "frame_t = 40 mm" comment "SKELETON P04 DECIDED: aluminium frame tube depth, walls and ceiling (PM ruling 2026-10-31 on outer_t)"
equation "outer_t = skin_t + bond_t + frame_t" comment "SKELETON P04 DECIDED: PM ruling 2026-10-31: ACP 3 + bond line 3 + frame 40, walls and ceiling (was 43)"
equation "cav_gap = 4 mm" comment "SKELETON P04 DECIDED: D-16, D-42: the gap between the outer panel and the lining cassette in the wall and ceiling stack"
equation "cass_t = 34 mm" comment "SKELETON P04 SOURCE: layout study B1 final list L-CASS 34 (tray + 25 gap + felt 9)"
equation "stack_t = outer_t + cav_gap + cass_t" comment "SKELETON P04 CALCULATION: D-16, D-42 stack, walls and ceiling: outer panel + cavity gap + cassette (PM ruling 2026-10-31 on outer_t)"
equation "wall_depth = 1495 mm" comment "SKELETON P04 DECIDED: PM ruling pass C: side walls start at the decor back plate (Y -645), as v1 (1496)"
equation "lin_gap = 4 mm" comment "SKELETON P04 ASSUMPTION: PM ruling pass C: gap above the upper side linings so they stay floating (= the 4 mm stack gap)"
equation "seam_gap = 2.26 mm" comment "SKELETON P04 DECIDED: PM ruling 2026-10-31 (Mechanical Checker F-001, F-005): the Joints Engineer's 2.26 mm at all nine site seam types, set by a metal stop (1.5 stop washer + 0.76 rivnut head; joints register section 2.8)"
equation "mat_t = 3 mm" comment "SKELETON P04 DECIDED: D-72, PM ruling 2026-10-31 (from BASE): the 3 mm floor mat under the floor ply"
equation "floor_t = 9 mm" comment "SKELETON P04 DECIDED: PM ruling 2026-10-31: 9 mm floor panels (was 15, layout study B1 list), on the mat"
equation "thresh_h = 13 mm" comment "SKELETON P04 DECIDED: PM ruling 2026-10-31: 13 mm, a US-accessible threshold (D-18 had 20); the kick strip keeps its kick_gap above it"
equation "thresh_d = 60 mm" comment "SKELETON P04 SOURCE: layout study B1 list B-THRESH 1176 x 60 x 20"
equation "decor_d = 205 mm" comment "SKELETON P04 SOURCE: v1 geometry per the PM ruling on D-39 (as v1; the drawings win): v1 decor-frame drawing frames 191 (left) and 197 (right) deep plus ACP and back plate = the v1 STEP shell, Y -850 to -645 = 205. D-39 and the B1 list say 230-235 (v1 BOM); see BUILD-RECORD-P02"
equation "dl_w = 278 mm" comment "SKELETON P04 SOURCE: B1 list F-DL 278 (v1 BOM DL)"
equation "dr_w = 1016 mm" comment "SKELETON P04 SOURCE: B1 list F-DR 1016 (v1 STEP solid 78)"
equation "dt_w = 1697 mm" comment "SKELETON P04 SOURCE: B1 list F-DT 1697 (v1 BOM DT)"
equation "dt_h = 280 mm" comment "SKELETON P04 SOURCE: B1 list F-DT 280"
equation "door_w = 1176 mm" comment "SKELETON P04 DECIDED: D-46"
equation "door_h = 2011 mm" comment "SKELETON P04 SOURCE: B1 list F-GLASS-DOOR 2011; v1 STEP solid 238"
equation "glass_t = 8.76 mm" comment "SKELETON P04 DECIDED: D-46 (4+4 laminate)"
equation "glass_y = 699 mm" comment "SKELETON P04 SOURCE: v1 STEP solid 238 centre Y = -699 (layout study data)"
equation "kick_d = 20 mm" comment "SKELETON P04 ASSUMPTION: kick strip envelope depth (D-40 gives the height only)"
equation "kick_gap = 7 mm" comment "SKELETON P04 SOURCE: FRONT door unit: 7 mm running gap between the threshold and the kick strip for the drop seal (Mechanical Checker F-002 on P03)"
equation "fr_dz = 17 mm" comment "SKELETON P04 CALCULATION: v1 front top 2417 (v2 frame) - pod_h 2400"
equation "door_xl = 289 mm" comment "SKELETON P04 SOURCE: V1-FRONT-FACETS: door left edge X -961 = -1250 + 289"
equation "door_xbr = 1464 mm" comment "SKELETON P04 SOURCE: V1-FRONT-FACETS: door bottom-right X 214"
equation "door_xtr = 1182 mm" comment "SKELETON P04 SOURCE: V1-FRONT-FACETS: door top-right X -68"
equation "door_zb = 122 mm - fr_dz" comment "SKELETON P04 SOURCE: V1-FRONT-FACETS: door bottom Z 122"
equation "door_zt = 2133 mm - fr_dz" comment "SKELETON P04 SOURCE: V1-FRONT-FACETS: door top Z 2133"
equation "glass_gap = 4 mm" comment "SKELETON P04 DECIDED: PM ruling 2026-10-31 on Mechanical Checker F-014: the fixed glass's free edge runs parallel to the door's slanted edge, 4.0 mm away (FRONT's glass in PR #28 is the reference)"
equation "fix_xbr = 302 mm" comment "SKELETON P04 SOURCE: V1-FRONT-FACETS: fixed glass bottom-right X 948 = 1250 - 302"
equation "fix_xk = 501 mm" comment "SKELETON P04 SOURCE: V1-FRONT-FACETS: fixed glass knee X 749 = 1250 - 501"
equation "fix_zk = 1538 mm - fr_dz" comment "SKELETON P04 SOURCE: V1-FRONT-FACETS: fixed glass knee Z 1538"
equation "fix_xtr = 1480 mm" comment "SKELETON P04 SOURCE: V1-FRONT-FACETS: fixed glass top-right X 230 = -1250 + 1480"
equation "fix_zb = 119 mm - fr_dz" comment "SKELETON P04 SOURCE: V1-FRONT-FACETS: fixed glass bottom Z 119"
equation "fix_zt = 2136 mm - fr_dz" comment "SKELETON P04 SOURCE: V1-FRONT-FACETS: fixed glass top Z 2136"
equation "dt_zb = 2137 mm - fr_dz" comment "SKELETON P04 SOURCE: V1-FRONT-FACETS: DT and DR edge above the glass Z 2137"
equation "ch_zlo = 2217 mm - fr_dz" comment "SKELETON P04 SOURCE: V1-FRONT-FACETS: top chamfer front edge Z 2217 at Y -848"
equation "ch_yb = 672 mm" comment "SKELETON P04 SOURCE: V1-FRONT-FACETS: top chamfer back edge Y -672"
equation "dl_x2 = 92 mm" comment "SKELETON P04 SOURCE: V1-FRONT-FACETS: DL facet knee X -1158 = -1250 + 92"
equation "dl_y2 = 752 mm" comment "SKELETON P04 SOURCE: V1-FRONT-FACETS: DL facet knee Y -752"
equation "dl_x3 = 271 mm" comment "SKELETON P04 SOURCE: V1-FRONT-FACETS: DL front corner X -979"
equation "dl_y3 = 844 mm" comment "SKELETON P04 SOURCE: V1-FRONT-FACETS: DL front corner Y -844"
equation "dl_y1 = 670 mm" comment "SKELETON P04 SOURCE: V1-FRONT-FACETS: DL outer facet start Y -670"
equation "dl_zo = 2414 mm - fr_dz" comment "SKELETON P04 SOURCE: V1-FRONT-FACETS: DL top at the outer corner Z 2414"
equation "dt_x2 = 281 mm" comment "SKELETON P04 SOURCE: V1-FRONT-FACETS: DT lower facet left X -969 = -1250 + 281"
equation "dt_y2 = 767 mm" comment "SKELETON P04 SOURCE: V1-FRONT-FACETS: DT lower facet left Y -767"
equation "dt_y3 = 753 mm" comment "SKELETON P04 SOURCE: V1-FRONT-FACETS: DT lower facet outer Y -753 at X -1154"
equation "dr_xc = 198 mm" comment "SKELETON P04 SOURCE: V1-FRONT-FACETS: DR corner facet front X 1052 = 1250 - 198"
equation "dt_xr = 1699 mm" comment "SKELETON P04 SOURCE: V1-FRONT-FACETS: DT/DR joint at the top, X 449 = -1250 + 1699 (PM ruling pass C)"
equation "dr_yc = 672 mm" comment "SKELETON P04 SOURCE: V1-FRONT-FACETS: DR corner facet back Y -672"